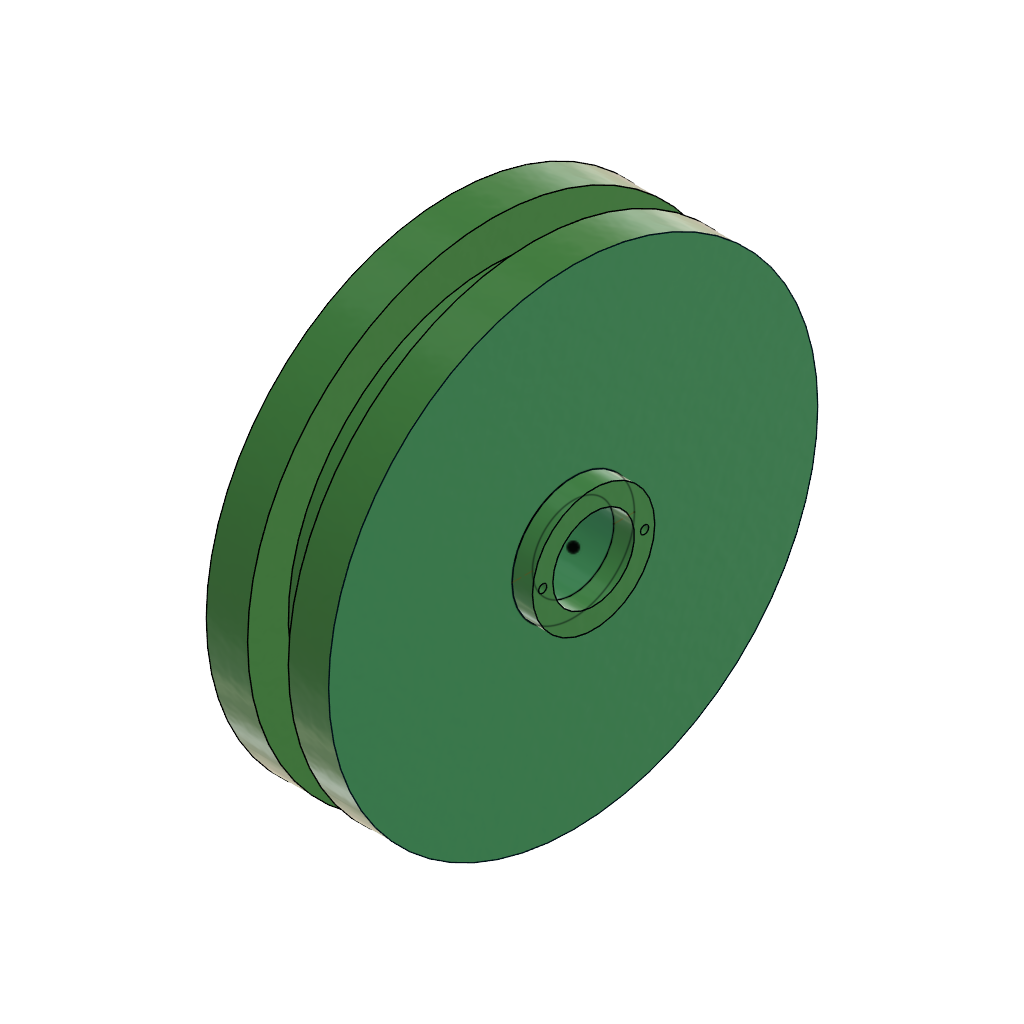
poulie (Autodesk Fusion 360 design; units mm, degrees)
part number: 2026-10-28-08-58-40-815
Autodesk Fusion 360 part; units mm, degrees
sketch "Esquisse1" plane through (0, 0, 0) normal (0, 1, 0) x (1, 0, 0)
  line L0 (-15.1645, 0) -> (-15.1645, -60)
  line L1 (14.8801, -60) -> (14.8801, 0)
  line L2 (14.8801, 0) -> (-15.1645, 0)
  line L3 (-5, -60) -> (-5, -50)
  line L4 (-5, -50) -> (5, -50)
  line L5 (5, -50) -> (5, -60)
  line L6 (-15.1645, -60) -> (-5, -60)
  line L7 (5, -60) -> (14.8801, -60)
  constraint vertical L0
  constraint perpendicular L0 L6
  constraint perpendicular L1 L7
  constraint perpendicular L0 L2
  constraint perpendicular L3 L6
  constraint perpendicular L3 L4
  constraint perpendicular L5 L7
  constraint collinear L6 L7
revolve "Révolution1" add sketch "Esquisse1" angle 360 about axis through (14.8801, 0, 0) along (-1, 0, 0)
sketch "Esquisse2" plane through (14.8801, 0, 0) normal (1, 0, 0) x (0, 1, 0)
  circle A0 centre (0, 0) radius 60
  circle A1 centre (0, 0) radius 10
  circle A2 centre (0, 0) radius 15
  line L0 (-15, 0) -> (-10, 0) construction
  line L1 (10, 0) -> (15, 0) construction
  dimension "d2" = 20
  dimension "d3" = 5
  constraint concentric A0 A1
  constraint coincident A2 L0.start
  constraint coincident A1 L0.end
  constraint perpendicular A1 L0
  constraint coincident A1 L1.start
  constraint coincident A2 L1.end
  constraint perpendicular A2 L1
  measures "d2" diameter of A1
extrude "Extrusion1" cut sketch "Esquisse2" against normal blind 80 contours A1
sketch "Esquisse3" plane through (-15.1645, 0, 0) normal (-1, 0, 0) x (0, -1, 0)
  circle A0 centre (0, 0) radius 10
  circle A1 centre (0, 0) radius 60
  circle A2 centre (0, 0) radius 15
  line L0 (15, 0) -> (10, 0)
  line L1 (-10, 0) -> (-15, 0)
  circle A3 centre (-12.5, 0) radius 1
  circle A4 centre (12.5, 0) radius 1
  dimension "d8" = 30
  dimension "d10" = 2
  dimension "d11" = 2
  constraint concentric A0 A2
  constraint coincident A2 L0.start
  constraint coincident A0 L0.end
  constraint perpendicular A0 L0
  constraint coincident A0 L1.start
  constraint coincident A2 L1.end
  constraint perpendicular A2 L1
  constraint midpoint L1 A3.centre
  constraint midpoint L0 A4.centre
  measures "d8" diameter of A2
  measures "d10" diameter of A3
  measures "d11" diameter of A4
extrude "Extrusion2" add sketch "Esquisse2" along normal blind 5 contours A2
extrude "Extrusion3" add sketch "Esquisse3" along normal blind 5 contours A0 A2 L0 L1 A3 A4 | A0 A2 L0 L1 A3 A4
extrude "Extrusion4" cut 2 faces at (-15.1645, 12.8074, 0.0497) (-15.1645, -12.1926, 0.0497) along direction (1, 0, 0) blind 190
